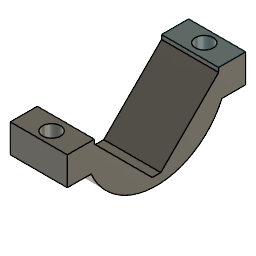
Drive Motor Mount Base (Autodesk Fusion 360 design; units mm, degrees)
Autodesk Fusion 360 part; units mm, degrees
ref_plane "WorkPlane1" through (0, 0, 0) normal (1, 0, 0) x (0, 1, 0)
sketch "Sketch3" plane through (0, 0, 0) normal (1, 0, 0) x (0, 1, 0)
  line L0 (-15.875, 0) -> (15.875, 0)
  line L1 (15.875, 0) -> (15.875, -12.7)
  line L2 (15.875, -12.7) -> (-15.875, -12.7)
  line L3 (-15.875, -12.7) -> (-15.875, 0)
  line L4 (-11.049, 0) -> (-11.049, -0.762)
  line L5 (-11.049, -0.762) -> (-0.762, -11.049)
  line L6 (-0.762, -11.049) -> (0.762, -11.049)
  line L7 (0.762, -11.049) -> (11.049, -0.762)
  line L8 (11.049, -0.762) -> (11.049, 0)
  dimension "d12" = 31.75
  dimension "d13" = 12.7
  dimension "d14" = 0.762
  dimension "d15" = 4.826
  dimension "d16" = 4.826
  dimension "d17" = 1.524
  constraint horizontal L0
  constraint vertical L1
  constraint horizontal L2
  constraint vertical L3
  constraint coincident L0 L4.start
  constraint perpendicular L0 L4
  constraint horizontal L6
  constraint coincident L0 L8.end
  constraint perpendicular L0 L8
  constraint equal L4 L8
  constraint equal L5 L7
  constraint perpendicular L5 L7
  constraint midpoint origin L0
  measures "d12" distance of L1.end L2.end
  measures "d13" distance of L0.start L2.end
  measures "d14" distance of L4.start L4.end
  measures "d15" distance of L0.start L4.start
  measures "d16" distance of L0.end L8.end
  measures "d17" distance of L5.end L6.end
extrude "Extrude2" add sketch "Sketch3" along normal blind 10.16 contours L0 L1 L2 L3 L4 L5 L6 L7 L8
sketch "Sketch4" plane through (0, 0, 0) normal (0, 0, 1) x (-1, 0, 0)
  line L0 (0, -15.875) -> (0, -11.049)
  line L1 (0, -11.049) -> (-10.16, -11.049)
  line L2 (-10.16, -11.049) -> (-10.16, -15.875)
  line L3 (-10.16, -15.875) -> (0, -15.875)
sketch "Sketch5" plane through (10.16, 0, 0) normal (1, 0, 0) x (0, -1, 0)
  line L0 (-11.049, 0.762) -> (-0.762, 11.049)
  line L1 (-0.762, 11.049) -> (0.762, 11.049)
  line L2 (0.762, 11.049) -> (11.049, 0.762)
  line L3 (11.049, 0.762) -> (11.049, 0)
  line L4 (11.049, 0) -> (15.875, 0)
  line L5 (15.875, 0) -> (15.875, 12.7)
  line L6 (15.875, 12.7) -> (-15.875, 12.7)
  line L7 (-15.875, 12.7) -> (-15.875, 0)
  line L8 (-15.875, 0) -> (-11.049, 0)
  line L9 (-11.049, 0) -> (-11.049, 0.762)
  arc A0 (-12.7, 0) -> (12.7, 0) centre (0, 0) ccw
  line L10 (-11.6397, -5.08) -> (15.875, -5.08)
  line L11 (11.6397, -5.08) -> (-15.875, -5.08)
  line L12 (-15.875, 0) -> (-11.049, 0)
  dimension "d21" = 5.08
  dimension "d22" = 5.08
  dimension "d34" = 12.7
  constraint coincident A0.centre origin
  constraint coincident L8 A0.end
  constraint coincident L4 A0.start
  constraint coincident A0 L10.start
  constraint coincident L5 L10.end
  constraint perpendicular L5 L10
  constraint coincident A0 L11.start
  constraint coincident L7 L11.end
  constraint perpendicular L7 L11
  measures "d21" distance of L4 L10
  measures "d22" distance of L11 L12
  measures "d34" radius of A0
extrude "Extrude3" add sketch "Sketch5" against normal up to surface (10.16 mm away) contours L0 L1 L2 L3 L4 L5 L6 L7 L8 L9 L12
sketch "Sketch7" plane through (0, 0, 0) normal (0, 0, 1) x (-1, 0, 0)
  line L0 (0, 11.049) -> (0, 15.875)
  line L1 (0, 15.875) -> (-10.16, 15.875)
  line L2 (-10.16, 15.875) -> (-10.16, 11.049)
  line L3 (-10.16, 11.049) -> (0, 11.049)
  circle A0 centre (-5.08, 13.589) radius 1.6
  circle A1 centre (-5.08, -13.589) radius 1.6
  line L4 (-10.16, -15.875) -> (0, -15.875)
  line L5 (-10.16, -11.049) -> (-10.16, -15.875)
  dimension "d35" = 3.2
  dimension "d36" = 3.2
  dimension "d37" = 2.286
  dimension "d38" = 2.286
  dimension "d39" = 5.08
  dimension "d40" = 5.08
  measures "d35" diameter of A1
  measures "d36" diameter of A0
  measures "d37" distance of A1.centre L4
  measures "d38" distance of L1 A0.centre
  measures "d39" distance of L2 A0.centre
  measures "d40" distance of A1.centre L5
extrude "Extrude5" cut sketch "Sketch7" against normal blind 12.7 contours A0 | A1
sketch "Sketch8" plane through (0, 0, 0) normal (-1, 0, 0) x (0, -1, 0)
  line L0 (-0.762, -11.049) -> (-11.049, -0.762)
  line L1 (-11.049, -0.762) -> (-11.049, 0)
  line L2 (-11.049, 0) -> (-15.875, 0)
  line L3 (-15.875, 0) -> (-15.875, -12.7)
  line L4 (-15.875, -12.7) -> (15.875, -12.7)
  line L5 (15.875, -12.7) -> (15.875, 0)
  line L6 (15.875, 0) -> (11.049, 0)
  line L7 (11.049, 0) -> (11.049, -0.762)
  line L8 (11.049, -0.762) -> (0.762, -11.049)
  line L9 (0.762, -11.049) -> (-0.762, -11.049)
  arc A0 (-12.7, 0) -> (12.7, 0) centre (0, 0) ccw
  line L10 (-11.6397, -5.08) -> (-15.875, -5.08)
  line L11 (11.6397, -5.08) -> (15.875, -5.08)
  line L12 (-15.875, 0) -> (-11.049, 0)
  dimension "d43" = 5.08
  dimension "d44" = 5.08
  constraint coincident A0.centre origin
  constraint tangent L4 A0
  constraint coincident L6 A0.end
  constraint coincident L2 A0.start
  constraint coincident A0 L10.start
  constraint coincident L3 L10.end
  constraint perpendicular L3 L10
  constraint coincident A0 L11.start
  constraint coincident L5 L11.end
  constraint perpendicular L5 L11
  measures "d43" distance of L10 L12
  measures "d44" distance of L6 L11
extrude "Extrude6" cut sketch "Sketch8" against normal blind 10.16 contours L3 L4 A0 L10 | L4 L5 A0 L11
